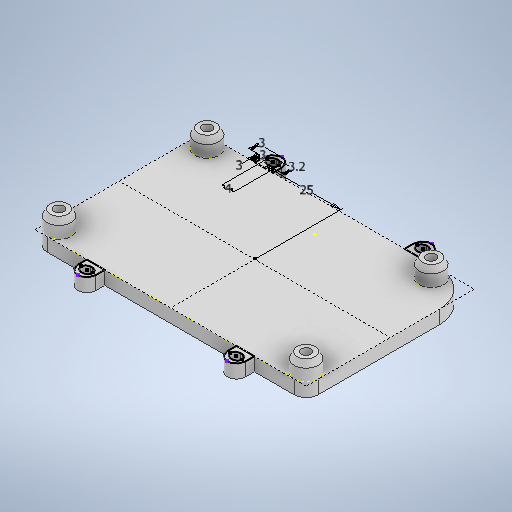
# Autodesk Inventor part: arduino_mega_standoffs_plate_m3_w_tabs
Saved by Autodesk Inventor 2025.1 (Build 291241000, 241)
## iProperties
Created: 2026-06-20
Part Number: arduino_mega_standoffs_plate_m3_w_tabs
Material: Generic
Document SubType Name: Modeling
Designer: Aiden
Density: 1 g/cm^3
Appearance: Default
Author: Aiden
Autodesk Inventor part; units mm, degrees
ref_plane "YZ Plane" through (0, 0, 0) normal (1, 0, 0) x (0, 1, 0)
ref_plane "XZ Plane" through (0, 0, 0) normal (0, 1, 0) x (-1, 0, 0)
ref_plane "XY Plane" through (0, 0, 0) normal (0, 0, 1) x (1, 0, 0)
sketch "Arduino Hole Layout" plane through (0, 0, 0) normal (0, 1, 0) x (-1, 0, 0)
  circle A0 centre (43.0199, -7.0958) radius 1.55 construction
  circle A1 centre (-31.8801, -7.0958) radius 1.55 construction
  circle A2 centre (44.3199, 41.1042) radius 1.55 construction
  circle A3 centre (-38.2801, 41.1042) radius 1.55 construction
  line L0 (58.8879, -10.055) -> (-40.7911, -10.055) construction
  line L1 (-40.7911, -10.055) -> (-40.7911, 44.0634) construction
  line L2 (-40.7911, 44.0634) -> (58.8879, 44.0634) construction
  line L3 (58.8879, 44.0634) -> (58.8879, -10.055) construction
  line L4 (43.0199, -7.0958) -> (43.0199, -10.055) construction
  line L5 (44.3199, 41.1042) -> (44.3199, 44.0634) construction
  dimension "d0" = 3.1
  dimension "d1" = 74.9
  dimension "d2" = 1.3
  dimension "d3" = 48.2
  dimension "d5" = 82.6
  dimension "d9" = 15.868
  dimension "d10" = 54.1184
  dimension "d11" = 99.679
  constraints: 12 end point, 4 centre point, 4 coincident, 3 equal radius, 3 parallel, 3 perpendicular, 2 horizontal alignment, 2 point on line, 1 horizontal
  measures "d0" diameter of A0
  measures "d1" distance of A1.centre L4.start
  measures "d2" horizontal distance of L5.start L4.start
  measures "d3" vertical distance of L4.start L5.start
  measures "d5" distance of A3.centre L5.start
  measures "d9" distance from line of L3 L4.start
  measures "d10" distance of L2.end L0.start
  measures "d11" distance of L1.end L2.end
sketch "Sketch13" plane through (0, 0, 0) normal (0, 1, 0) x (-1, 0, 0)
  circle A0 centre (43.0199, -7.0958) radius 1.55 construction
  circle A1 centre (43.0199, -7.0958) radius 4
  point P0 (0, 0)
  point P1 (-38.2801, 41.1042)
  point P2 (-31.8801, -7.0958)
  point P3 (-38.2801, 41.1042)
  point P4 (44.3199, 41.1042)
  dimension "d48" = 8
  constraints: 1 centre point, 1 coincident
  measures "d48" diameter of A1
extrude "Extrusion10" add sketch "Sketch13" along normal blind 6
sketch "Sketch14" plane through (-43.0199, 6, -7.0958) normal (0, 1, 0) x (1, 0, 0)
  circle A0 centre (0, 0) radius 4 construction
  point P0 (43.0199, -7.0958)
  point P1 (81.3, -48.2)
  point P2 (-1.3, -48.2)
  point P3 (74.9, 0)
  point P4 (81.3, -48.2)
  point P5 (-1.3, -48.2)
  constraints: 3 coincident
hole "Hole2" at (-43.0199, 6, -7.0958) direction (0, -1, 0) diameter 3.25 depth 5 tip angle 118
chamfer "Chamfer2" distance 1 distance2 2 1 edges at (-39.0199, 6, -7.0958) measured on face at (-39.5199, 6, -7.0958)
pattern_sketch "Sketch Driven Pattern1" from (-43.0199, 0, -7.0958) copies at (-44.3199, 0, 41.1042) at (31.8801, 0, -7.0958) at (38.2801, 0, 41.1042)
sketch "Sketch16" plane through (-44.3199, 0, 41.1042) normal (0, -1, 0) x (1, 0, 0)
  line L0 (-4, 4) -> (86.6, 4)
  line L1 (86.6, 4) -> (86.6, -52.2)
  line L2 (86.6, -52.2) -> (-4, -52.2)
  line L3 (-4, -52.2) -> (-4, 4)
  circle A0 centre (0, 0) radius 4 projected
  circle A1 centre (82.6, 0) radius 4 projected
  circle A2 centre (1.3, -48.2) radius 4 projected
  arc A3 (-4, -46.9) -> (1.3, -52.2) centre (1.3, -46.9) ccw
  arc A4 (73.0608, -52.2) -> (86.6, -40.521) centre (74.7932, -40.521) ccw
  circle A5 centre (76.2, -48.2) radius 4 projected
  point P0 (44.3199, -41.1042)
  point P1 (76.9208, -52.1345)
  point P2 (86.6, 0)
  point P3 (82.6, 4)
  point P4 (0, 4)
  point P5 (-4, 0)
  point P6 (76.2, -52.2)
  constraints: 8 end point, 5 tangent, 4 point on circle, 4 point on line, 2 centre point, 2 horizontal, 2 parallel, 1 perpendicular, 1 vertical alignment, 4 other
extrude "Extrusion12" add sketch "Sketch16" along normal blind 4.5 contours A2 | L0 A1 L1 A4 A5 L2 A3 L3 A0 | A0 | A1 | A5
sketch "Sketch17" plane through (-44.3199, 0, 41.1042) normal (0, 1, 0) x (1, 0, 0)
  line L0 (-4, 52.2) -> (86.6, 52.2) construction
  line L1 (86.6, 52.2) -> (86.6, -4) construction
  line L2 (86.6, -4) -> (-4, -4) construction
  line L3 (-4, -4) -> (-4, 52.2) construction
  circle A0 centre (1.3, 48.2) radius 4 construction
  circle A1 centre (76.2, 48.2) radius 4 construction
  circle A2 centre (82.6, 0) radius 4 construction
  circle A3 centre (0, 0) radius 4 construction
  line L4 (41.3, 52.2) -> (41.3, -4) construction
  line L5 (82.6, -4) -> (0, -4) construction
  line L6 (-4, 24.1) -> (86.6, 24.1) construction
  line L7 (15.9, 55.2) -> (16.7, 55.2) construction
  line L8 (15.9, 53.6) -> (16.7, 53.6)
  line L9 (16.7, 56.8) -> (15.9, 56.8)
  arc A4 (15.9, 56.8) -> (15.9, 53.6) centre (15.9, 55.2) ccw
  arc A5 (16.7, 53.6) -> (16.7, 56.8) centre (16.7, 55.2) ccw
  arc A6 (19.3, 55.2) -> (13.3, 55.2) centre (16.3, 55.2) ccw
  line L10 (13.3, 55.2) -> (13.3, 52.2)
  line L11 (19.3, 55.2) -> (19.3, 52.2)
  line L12 (19.3, 52.2) -> (13.3, 52.2)
  line L13 (66.7, 55.2) -> (65.9, 55.2) construction
  line L14 (66.7, 53.6) -> (65.9, 53.6)
  line L15 (65.9, 56.8) -> (66.7, 56.8)
  arc A7 (66.7, 53.6) -> (66.7, 56.8) centre (66.7, 55.2) ccw
  arc A8 (65.9, 56.8) -> (65.9, 53.6) centre (65.9, 55.2) ccw
  arc A9 (69.3, 55.2) -> (63.3, 55.2) centre (66.3, 55.2) ccw
  line L16 (69.3, 55.2) -> (69.3, 52.2)
  line L17 (63.3, 55.2) -> (63.3, 52.2)
  line L18 (63.3, 52.2) -> (69.3, 52.2)
  line L19 (15.9, -7) -> (16.7, -7) construction
  line L20 (15.9, -5.4) -> (16.7, -5.4)
  line L21 (16.7, -8.6) -> (15.9, -8.6)
  arc A10 (15.9, -5.4) -> (15.9, -8.6) centre (15.9, -7) ccw
  arc A11 (16.7, -8.6) -> (16.7, -5.4) centre (16.7, -7) ccw
  arc A12 (13.3, -7) -> (19.3, -7) centre (16.3, -7) ccw
  line L22 (13.3, -7) -> (13.3, -4)
  line L23 (19.3, -7) -> (19.3, -4)
  line L24 (19.3, -4) -> (13.3, -4)
  line L25 (66.7, -5.4) -> (65.9, -5.4)
  line L26 (63.3, -4) -> (69.3, -4)
  line L27 (69.3, -7) -> (69.3, -4)
  line L28 (63.3, -7) -> (63.3, -4)
  line L29 (66.7, -7) -> (65.9, -7) construction
  arc A13 (66.7, -8.6) -> (66.7, -5.4) centre (66.7, -7) ccw
  arc A14 (65.9, -5.4) -> (65.9, -8.6) centre (65.9, -7) ccw
  line L30 (65.9, -8.6) -> (66.7, -8.6)
  arc A15 (63.3, -7) -> (69.3, -7) centre (66.3, -7) ccw
  point P0 (44.3199, 41.1042)
  point P1 (14.3, 55.2)
  point P2 (18.3, 55.2)
  point P3 (41.3, 24.1)
  point P4 (41.3, 24.1)
  point P5 (16.3, 58.2)
  point P6 (68.3, 55.2)
  point P7 (64.3, 55.2)
  point P8 (66.3, 58.2)
  point P9 (14.3, -7)
  point P10 (18.3, -7)
  point P11 (16.3, -10)
  point P12 (68.3, -7)
  point P13 (64.3, -7)
  point P14 (66.3, -10)
  dimension "d74" = 3.2
  dimension "d76" = 4
  dimension "d77" = 25
  dimension "d79" = 3
  dimension "d80" = 3
  dimension "d81" = 3
  constraints: 68 end point, 48 symmetric about line, 31 point on circle, 12 centre point, 11 tangent, 7 midpoint, 4 coincident, 3 parallel, 2 horizontal, 2 perpendicular, 2 point on line, 1 collinear, 1 vertical, 9 other
  measures "d74" distance between parallel lines of L8 L9
  measures "d76" distance of point (14.3, 55.2) point (18.3, 55.2)
  measures "d77" horizontal distance of point (41.3, 24.1) point (16.3, 55.2)
  measures "d79" distance from line of L0 point (16.3, 55.2)
  measures "d80" distance of point (16.3, 58.2) point (16.3, 55.2)
  measures "d81" distance of L10.start L10.end
extrude "Extrusion13" add sketch "Sketch17" against normal up to surface (4.5 mm away)
body "Solid3"
